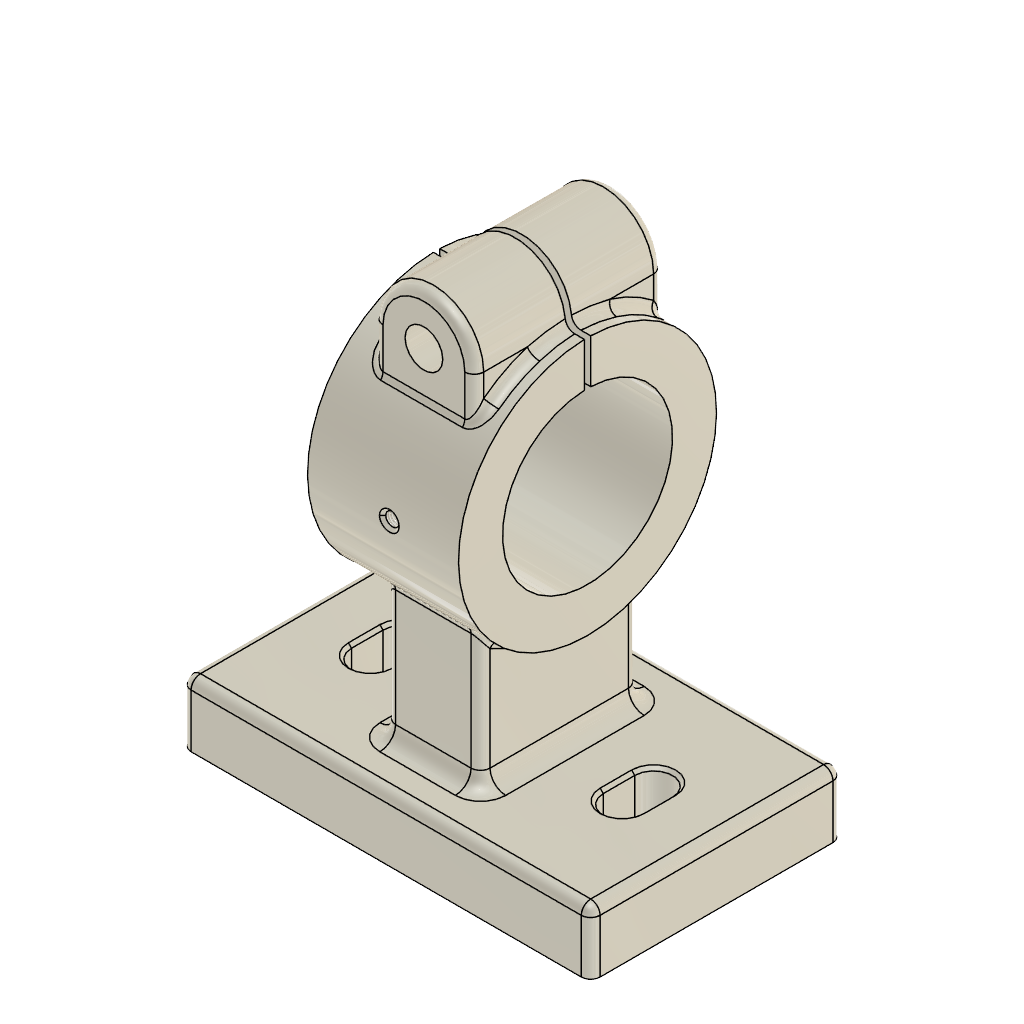
guide_mecanique (Autodesk Fusion 360 design; units mm, degrees)
part number: 2026-10-31-16-26-16-089
Autodesk Fusion 360 part; units mm, degrees
sketch "Esquisse1" plane through (0, 0, 0) normal (0, 0, 1) x (1, 0, 0)
  line L0 (65, -40) -> (-65, -40)
  line L1 (-65, -40) -> (-65, 40)
  line L2 (-65, 40) -> (65, 40)
  line L3 (65, 40) -> (65, -40)
  line L4 (65, -40) -> (-65, 40) construction
  line L5 (-65, -40) -> (65, 40) construction
  dimension "d1" = 130
  dimension "d2" = 80
  constraint horizontal L0
  constraint perpendicular L0 L1
  constraint parallel L0 L2
  constraint parallel L1 L3
  constraint coincident L4 origin
  constraint coincident L5 origin
  measures "d1" distance of L1.end L2.end
  measures "d2" distance of L0.end L1.end
extrude "Extrusion1" add sketch "Esquisse1" against normal blind 20 makes body 1
sketch "Esquisse2" plane through (0, 0, 0) normal (1, 0, 0) x (0, 1, 0)
  circle A0 centre (0, 76) radius 27
  circle A1 centre (0, 76) radius 41
  line L0 (40, -20) -> (-40, -20)
  dimension "d6" = 54
  dimension "d7" = 82
  dimension "d8" = 96
  constraint concentric A0 A1
  constraint vertical origin A0.centre
  measures "d6" diameter of A0
  measures "d7" diameter of A1
  measures "d8" distance of A0.centre L0
extrude "Extrusion2" add sketch "Esquisse2" along normal mid plane 48 separate body makes body 2
sketch "Esquisse3" plane through (0, 0, 0) normal (0, 0, 1) x (-1, 0, 0)
  line L0 (-65, -40) -> (65, -40)
  line L1 (65, -40) -> (65, 40)
  line L2 (65, 40) -> (-65, 40)
  line L3 (-65, 40) -> (-65, -40)
  line L4 (-15, 25) -> (15, 25)
  line L5 (15, 25) -> (15, -25)
  line L6 (15, -25) -> (-15, -25)
  line L7 (-15, -25) -> (-15, 25)
  line L8 (-15, 25) -> (15, -25) construction
  line L9 (15, 25) -> (-15, -25) construction
  dimension "d11" = 30
  dimension "d12" = 50
  constraint horizontal L4
  constraint perpendicular L4 L5
  constraint parallel L4 L6
  constraint parallel L5 L7
  constraint coincident L8 origin
  constraint coincident L9 origin
  measures "d11" distance of L5.end L6.end
  measures "d12" distance of L4.end L5.end
extrude "Extrusion3" add sketch "Esquisse3" along normal up to near side of body 2 contours L4 L5 L6 L7 bodies 1 2
sketch "Esquisse4" plane through (0, 0, 0) normal (0, 0, 1) x (-1, 0, 0)
  line L0 (15, 25) -> (15, -25)
  line L1 (15, -25) -> (-15, -25)
  line L2 (-15, -25) -> (-15, 25)
  line L3 (-15, 25) -> (15, 25)
  line L4 (-65, -40) -> (65, -40)
  line L5 (65, -40) -> (65, 40)
  line L6 (65, 40) -> (-65, 40)
  line L7 (-65, 40) -> (-65, -40)
  line L8 (-34, -5) -> (-34, 5)
  arc A0 (-34, 5) -> (-46, 5) centre (-40, 5) ccw
  line L9 (-46, 5) -> (-46, -5)
  arc A1 (-46, -5) -> (-34, -5) centre (-40, -5) ccw
  line L10 (-40, -11) -> (-40, 11) construction
  dimension "d16" = 12
  dimension "d17" = 25
  dimension "d18" = 35
  dimension "d19" = 10
  constraint tangent L8 A0
  constraint tangent A0 L9
  constraint parallel L8 L9
  constraint tangent L9 A1
  constraint tangent L8 A1
  constraint coincident A1 L10.start
  constraint coincident A0 L10.end
  constraint coincident A0.centre L10
  constraint coincident A1.centre L10
  constraint vertical L10
  measures "d16" distance of L8 L9
  measures "d17" distance of L7 A1.centre
  measures "d18" distance of L4 A1.centre
  measures "d19" distance of A1.centre A0.centre
extrude "Extrusion4" cut sketch "Esquisse4" against normal up to surface (20 mm away) contours L8 A0 L9 A1 bodies 1
chamfer "Chanfrein1" distance 1 angle 45 4 edges at (34, 0, 0) (40, 11, 0) (46, 0, 0) (40, -11, 0) tangent chain off on bodies 1
mirror "Symétrie miroir1" about plane through (0, 0, 0) normal (1, 0, 0) of "Extrusion4", "Chanfrein1"
sketch "Esquisse5" plane through (0, 0, 0) normal (0, 1, 0) x (1, 0, 0)
  circle A0 centre (2, -118) radius 6
  circle A1 centre (2, -118) radius 16
  line L0 (65, 20) -> (-65, 20)
  line L1 (24, -117) -> (24, -35)
  line L2 (-14, -118) -> (18, -118)
  line L3 (18, -118) -> (18, -95)
  line L4 (18, -95) -> (-14, -95)
  line L5 (-14, -95) -> (-14, -118)
  dimension "d25" = 138
  dimension "d26" = 22
  dimension "d27" = 12
  dimension "d28" = 32
  constraint concentric A0 A1
  constraint horizontal L2
  constraint vertical L3
  constraint horizontal L4
  constraint vertical L5
  constraint coincident A0.centre L2
  constraint tangent A1 L3
  constraint tangent A1 L5
  measures "d25" distance of A0.centre L0
  measures "d26" distance of A0.centre L1
  measures "d27" diameter of A0
  measures "d28" diameter of A1
extrude "Extrusion5" add sketch "Esquisse5" along normal mid plane 60 contours A0 A1 L2 | A0 A1 L2 | A1 L3 L4 L5 bodies 1
delete_face "DeleteFace1" 1 faces at (18, -3.1636, 98.7929) on bodies 1
delete_face "DeleteFace2" 1 faces at (0.053, -2.5955, 116.9178) on bodies 1
fillet "Congé1" radius 3 4 edges at (65, 40, -10) (-65, 40, -10) (65, -40, -10) (-65, -40, -10) on bodies 1
fillet "Congé1" radius 3 4 edges at (-15, 25, 21.7519) (15, 25, 21.7519) (-15, -25, 21.7519) (15, -25, 21.7519) on bodies 1
fillet "Congé1" radius 3 4 edges at (0, 40, 0) (-65, 0, 0) (0, -40, 0) (65, 0, 0) on bodies 1
fillet "Congé2" radius 5 8 edges at (14.1213, -24.1213, 0) (0, -25, 0) (-14.1213, -24.1213, 0) (-15, 0, 0) (-14.1213, 24.1213, 0) (0, 25, 0) (14.1213, 24.1213, 0) (15, 0, 0) on bodies 1
fillet "Congé2" radius 3 8 edges at (14.2007, 24.0385, 42.7864) (0, 25, 43.5038) (-14.2007, 24.0385, 42.7864) (-15, 0, 35) (-14.2007, -24.0385, 42.7864) (0, -25, 43.5038) (14.2007, -24.0385, 42.7864) (15, 0, 35) on bodies 1
fillet "Congé3" radius 3 6 edges at (18, -30, 110.9732) (2, -30, 134) (-14, -30, 110.9732) (-14, 30, 110.9732) (2, 30, 134) (18, 30, 110.9732) on bodies 1
fillet "Congé4" radius 3 8 edges at (17.2477, -28.9865, 104.9961) (2, -30, 103.9464) (-13.2439, -28.991, 104.9917) (-14, 0, 117) (-13.2439, 28.991, 104.9917) (2, 30, 103.9464) (17.2477, 28.9865, 104.9961) (18, 0, 117) on bodies 1
sketch "Esquisse6" plane through (0, 0, 0) normal (1, 0, 0) x (0, 1, 0)
  line L0 (-1, 134.687) -> (1, 134.687)
  line L1 (1, 134.687) -> (1, 64.8319)
  line L2 (1, 64.8319) -> (-1, 64.8319)
  line L3 (-1, 64.8319) -> (-1, 134.687)
  line L4 (0, 0) -> (0, 64.8319) construction
  dimension "d45" = 2
  constraint horizontal L0
  constraint vertical L1
  constraint horizontal L2
  constraint vertical L3
  constraint coincident L4.start origin
  constraint vertical L4
  constraint midpoint L2 L4.end
  measures "d45" distance of L0.start L0.end
extrude "Extrusion6" cut sketch "Esquisse6" along normal through all and the other way through all bodies 1
ref_plane "Plan de construction1" through (0, -41, 76) normal (0, -1, 0) x (0, 0, -1)
sketch "Esquisse7" plane through (0, -41, 0) normal (0, -1, 0) x (-1, 0, 0)
  line L0 (-62, 20) -> (62, 20)
  line L1 (-24, -35) -> (-24, -116.9878)
  point P0 (-2, -76)
  dimension "d49" = 96
  dimension "d50" = 22
  measures "d49" distance of P0 L0
  measures "d50" distance of P0 L1
hole "Perçage1" at (2, -41, 76) direction (0, 1, 0) diameter 4.234 depth 40 tip angle 118 bodies 1
thread "Filetage1" "ISO Metric profile 5.0 M5x0.8 M5x0.8 6H" thread offset 0 thread depth 7.4
chamfer "Chanfrein2" distance 1 angle 45 2 edges at (2, -40.9453, 73.883) (2, -40.9453, 78.117) tangent chain off on bodies 1
equation "d6 = ( 27 * 2 ) * 1 mm"
equation "d7 = ( 41 * 2 ) * 1 mm"
equation "d28 = ( 16 * 2 ) * 1 mm"
